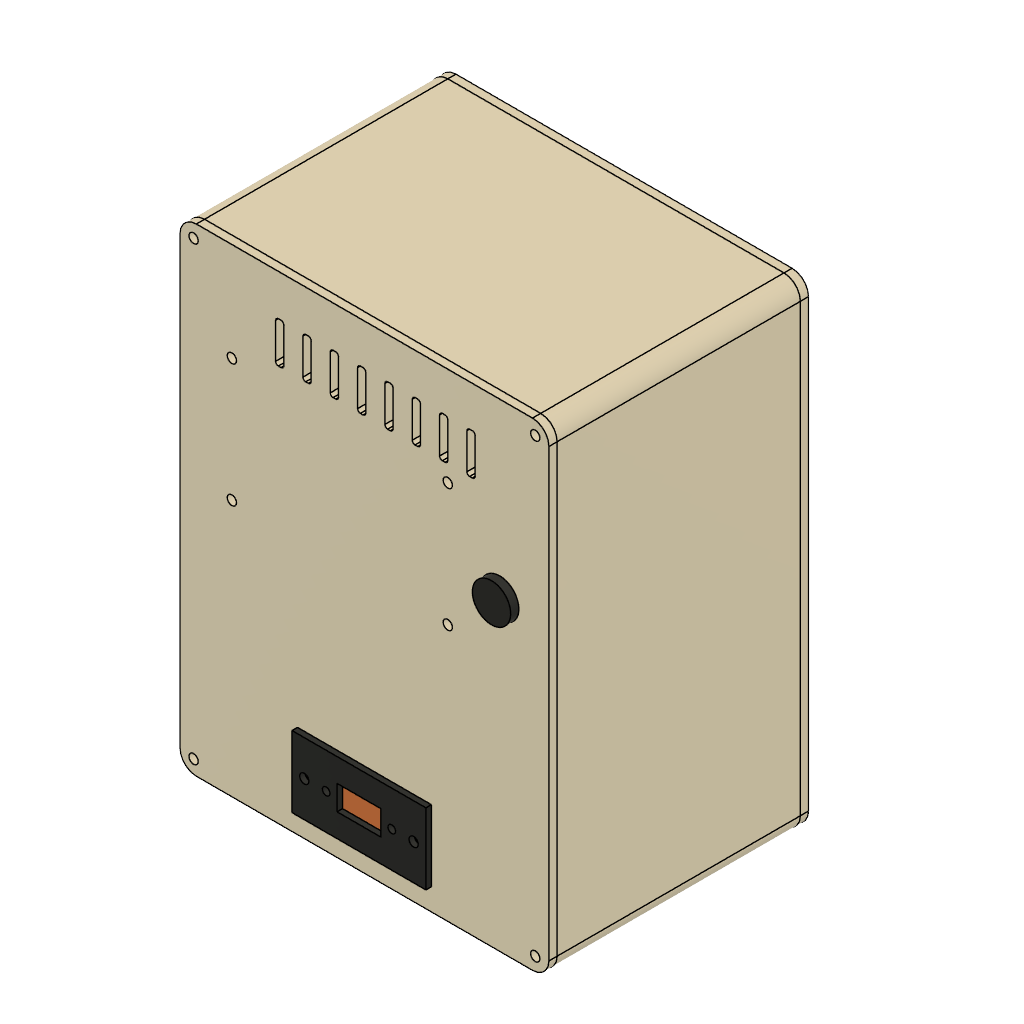
ORBIT-RevE (Autodesk Fusion 360 design; units mm, degrees)
part number: 2026-10-14-14-58-19-542
part number: 2026-10-14-14-58-21-077
part number: 2026-10-14-14-58-21-708
part number: 2026-10-14-14-58-23-821
part number: 2026-10-14-14-58-27-819
part number: 2026-10-14-14-58-51-787
part number: 2026-10-14-14-58-59-110
part number: 2026-10-14-14-59-02-449
part number: 2026-10-14-14-59-14-843
part number: 2026-10-14-14-59-18-859
part number: 2026-10-14-14-59-19-544
part number: 2026-10-14-14-59-20-250
part number: 2026-10-14-14-59-22-193
part number: 2026-10-14-14-59-22-958
part number: 2026-10-14-14-59-23-725
part number: 2026-10-14-14-59-25-713
part number: 2026-10-14-14-59-27-728
part number: 2026-10-14-14-59-28-510
part number: 2026-10-14-14-59-43-921
part number: 2026-10-14-14-59-48-721
part number: 2026-10-14-14-59-50-918
part number: 2026-10-14-14-59-55-353
part number: 2026-10-14-15-01-58-872
part number: 2026-10-14-15-01-59-865
part number: 2026-10-14-15-02-02-535
part number: 2026-10-14-15-02-03-536
part number: 2026-10-14-15-02-06-238
part number: 2026-10-14-15-02-08-109
part number: 2026-10-14-15-02-09-179
Autodesk Fusion 360 part; units mm, degrees
(part 1 of 2)
ref_plane "WorkPlane1" through (0, 0, 0) normal (0, 0, 1) x (1, 0, 0) in component "01 Ivory front panel"
sketch "Front panel" plane through (0, 0, 0) normal (0, 0, 1) x (1, 0, 0) in component "01 Ivory front panel"
  line L0 (6, 0) -> (129, 0)
  arc A0 (129, 0) -> (135, 6) centre (129, 6) ccw
  line L1 (135, 6) -> (135, 169)
  arc A1 (135, 169) -> (129, 175) centre (129, 169) ccw
  line L2 (129, 175) -> (6, 175)
  arc A2 (6, 175) -> (0, 169) centre (6, 169) ccw
  line L3 (0, 169) -> (0, 6)
  arc A3 (0, 6) -> (6, 0) centre (6, 6) ccw
extrude "Front panel (1)" add sketch "Front panel" along normal blind 3 makes body 1 in component "01 Ivory front panel"
ref_plane "WorkPlane2" through (0, 0, 0) normal (0, 0, 1) x (1, 0, 0) in component "01 Ivory front panel"
sketch "Adafruit 2050 landscape aperture" plane through (0, 0, 0) normal (0, 0, 1) x (1, 0, 0) in component "01 Ivory front panel"
  line L0 (30.9, 96.1) -> (104.1, 96.1)
  arc A0 (104.1, 96.1) -> (104.3, 96.3) centre (104.1, 96.3) ccw
  line L1 (104.3, 96.3) -> (104.3, 145.7)
  arc A1 (104.3, 145.7) -> (104.1, 145.9) centre (104.1, 145.7) ccw
  line L2 (104.1, 145.9) -> (30.9, 145.9)
  arc A2 (30.9, 145.9) -> (30.7, 145.7) centre (30.9, 145.7) ccw
  line L3 (30.7, 145.7) -> (30.7, 96.3)
  arc A3 (30.7, 96.3) -> (30.9, 96.1) centre (30.9, 96.3) ccw
extrude "Adafruit 2050 landscape aperture (1)" cut sketch "Adafruit 2050 landscape aperture" along normal blind 3 bodies 1 in component "01 Ivory front panel"
ref_plane "WorkPlane3" through (0, 0, 0) normal (0, 0, 1) x (1, 0, 0) in component "01 Ivory front panel"
sketch "Encoder" plane through (0, 0, 0) normal (0, 0, 1) x (1, 0, 0) in component "01 Ivory front panel"
  circle A0 centre (36, 36) radius 3.7
extrude "Encoder (1)" cut sketch "Encoder" along normal blind 3 bodies 1 in component "01 Ivory front panel"
ref_plane "WorkPlane4" through (0, 0, 0) normal (0, 0, 1) x (1, 0, 0) in component "01 Ivory front panel"
sketch "Pot" plane through (0, 0, 0) normal (0, 0, 1) x (1, 0, 0) in component "01 Ivory front panel"
  circle A0 centre (99, 36) radius 3.7
extrude "Pot (1)" cut sketch "Pot" along normal blind 3 bodies 1 in component "01 Ivory front panel"
ref_plane "WorkPlane5" through (0, 0, 0) normal (0, 0, 1) x (1, 0, 0) in component "01 Ivory front panel"
sketch "HOLD" plane through (0, 0, 0) normal (0, 0, 1) x (1, 0, 0) in component "01 Ivory front panel"
  circle A0 centre (18, 70) radius 3.2
extrude "HOLD (1)" cut sketch "HOLD" along normal blind 3 bodies 1 in component "01 Ivory front panel"
ref_plane "WorkPlane6" through (0, 0, 0) normal (0, 0, 1) x (1, 0, 0) in component "01 Ivory front panel"
sketch "GRID" plane through (0, 0, 0) normal (0, 0, 1) x (1, 0, 0) in component "01 Ivory front panel"
  circle A0 centre (117, 70) radius 3.2
extrude "GRID (1)" cut sketch "GRID" along normal blind 3 bodies 1 in component "01 Ivory front panel"
ref_plane "WorkPlane7" through (0, 0, 0) normal (0, 0, 1) x (1, 0, 0) in component "01 Ivory front panel"
sketch "Decorative disk slot" plane through (0, 0, 0) normal (0, 0, 1) x (1, 0, 0) in component "01 Ivory front panel"
  line L0 (51.5, 16) -> (83.5, 16)
  arc A0 (83.5, 16) -> (84.5, 17) centre (83.5, 17) ccw
  line L1 (84.5, 17) -> (84.5, 17.4)
  arc A1 (84.5, 17.4) -> (83.5, 18.4) centre (83.5, 17.4) ccw
  line L2 (83.5, 18.4) -> (51.5, 18.4)
  arc A2 (51.5, 18.4) -> (50.5, 17.4) centre (51.5, 17.4) ccw
  line L3 (50.5, 17.4) -> (50.5, 17)
  arc A3 (50.5, 17) -> (51.5, 16) centre (51.5, 17) ccw
extrude "Decorative disk slot (1)" cut sketch "Decorative disk slot" along normal blind 0.8 bodies 1 in component "01 Ivory front panel"
ref_plane "WorkPlane8" through (0, 0, 0) normal (0, 0, 1) x (1, 0, 0) in component "01 Ivory front panel"
sketch "M3 panel screw" plane through (0, 0, 0) normal (0, 0, 1) x (1, 0, 0) in component "01 Ivory front panel"
  circle A0 centre (5, 5) radius 1.7
extrude "M3 panel screw (1)" cut sketch "M3 panel screw" along normal blind 3 bodies 1 in component "01 Ivory front panel"
ref_plane "WorkPlane9" through (0, 0, 0) normal (0, 0, 1) x (1, 0, 0) in component "01 Ivory front panel"
sketch "M3 panel screw (1)" plane through (0, 0, 0) normal (0, 0, 1) x (1, 0, 0) in component "01 Ivory front panel"
  circle A0 centre (130, 5) radius 1.7
extrude "M3 panel screw (2)" cut sketch "M3 panel screw (1)" along normal blind 3 bodies 1 in component "01 Ivory front panel"
ref_plane "WorkPlane10" through (0, 0, 0) normal (0, 0, 1) x (1, 0, 0) in component "01 Ivory front panel"
sketch "M3 panel screw (2)" plane through (0, 0, 0) normal (0, 0, 1) x (1, 0, 0) in component "01 Ivory front panel"
  circle A0 centre (5, 170) radius 1.7
extrude "M3 panel screw (3)" cut sketch "M3 panel screw (2)" along normal blind 3 bodies 1 in component "01 Ivory front panel"
ref_plane "WorkPlane11" through (0, 0, 0) normal (0, 0, 1) x (1, 0, 0) in component "01 Ivory front panel"
sketch "M3 panel screw (3)" plane through (0, 0, 0) normal (0, 0, 1) x (1, 0, 0) in component "01 Ivory front panel"
  circle A0 centre (130, 170) radius 1.7
extrude "M3 panel screw (4)" cut sketch "M3 panel screw (3)" along normal blind 3 bodies 1 in component "01 Ivory front panel"
ref_plane "WorkPlane1" through (0, 0, 3) normal (0, 0, 1) x (1, 0, 0) in component "02 Ivory shell"
sketch "Shell exterior" plane through (0, 0, 3) normal (0, 0, 1) x (1, 0, 0) in component "02 Ivory shell"
  line L0 (6, 0) -> (129, 0)
  arc A0 (129, 0) -> (135, 6) centre (129, 6) ccw
  line L1 (135, 6) -> (135, 169)
  arc A1 (135, 169) -> (129, 175) centre (129, 169) ccw
  line L2 (129, 175) -> (6, 175)
  arc A2 (6, 175) -> (0, 169) centre (6, 169) ccw
  line L3 (0, 169) -> (0, 6)
  arc A3 (0, 6) -> (6, 0) centre (6, 6) ccw
extrude "Shell exterior (1)" add sketch "Shell exterior" along normal blind 89 separate body makes body 2 in component "02 Ivory shell"
ref_plane "WorkPlane2" through (0, 0, 3) normal (0, 0, 1) x (1, 0, 0) in component "02 Ivory shell"
sketch "Open cavity" plane through (0, 0, 3) normal (0, 0, 1) x (1, 0, 0) in component "02 Ivory shell"
  line L0 (6, 2.4) -> (129, 2.4)
  arc A0 (129, 2.4) -> (132.6, 6) centre (129, 6) ccw
  line L1 (132.6, 6) -> (132.6, 169)
  arc A1 (132.6, 169) -> (129, 172.6) centre (129, 169) ccw
  line L2 (129, 172.6) -> (6, 172.6)
  arc A2 (6, 172.6) -> (2.4, 169) centre (6, 169) ccw
  line L3 (2.4, 169) -> (2.4, 6)
  arc A3 (2.4, 6) -> (6, 2.4) centre (6, 6) ccw
extrude "Open cavity (1)" cut sketch "Open cavity" along normal blind 89 bodies 2 in component "02 Ivory shell"
ref_plane "WorkPlane3" through (0, 0, 3) normal (0, 0, 1) x (1, 0, 0) in component "02 Ivory shell"
sketch "M3 corner boss" plane through (0, 0, 3) normal (0, 0, 1) x (1, 0, 0) in component "02 Ivory shell"
  circle A0 centre (5, 5) radius 4
extrude "M3 corner boss (1)" add sketch "M3 corner boss" along normal blind 8 bodies 2 in component "02 Ivory shell"
ref_plane "WorkPlane4" through (0, 0, 3) normal (0, 0, 1) x (1, 0, 0) in component "02 Ivory shell"
sketch "M3 boss bore" plane through (0, 0, 3) normal (0, 0, 1) x (1, 0, 0) in component "02 Ivory shell"
  circle A0 centre (5, 5) radius 1.7
extrude "M3 boss bore (1)" cut sketch "M3 boss bore" along normal blind 8 bodies 2 in component "02 Ivory shell"
ref_plane "WorkPlane5" through (0, 0, 84) normal (0, 0, 1) x (1, 0, 0) in component "02 Ivory shell"
sketch "M3 corner boss (1)" plane through (0, 0, 84) normal (0, 0, 1) x (1, 0, 0) in component "02 Ivory shell"
  circle A0 centre (5, 5) radius 4
extrude "M3 corner boss (2)" add sketch "M3 corner boss (1)" along normal blind 8 bodies 2 in component "02 Ivory shell"
ref_plane "WorkPlane6" through (0, 0, 84) normal (0, 0, 1) x (1, 0, 0) in component "02 Ivory shell"
sketch "M3 boss bore (1)" plane through (0, 0, 84) normal (0, 0, 1) x (1, 0, 0) in component "02 Ivory shell"
  circle A0 centre (5, 5) radius 1.7
extrude "M3 boss bore (2)" cut sketch "M3 boss bore (1)" along normal blind 8 bodies 2 in component "02 Ivory shell"
ref_plane "WorkPlane7" through (0, 0, 3) normal (0, 0, 1) x (1, 0, 0) in component "02 Ivory shell"
sketch "M3 corner boss (2)" plane through (0, 0, 3) normal (0, 0, 1) x (1, 0, 0) in component "02 Ivory shell"
  circle A0 centre (130, 5) radius 4
extrude "M3 corner boss (3)" add sketch "M3 corner boss (2)" along normal blind 8 bodies 2 in component "02 Ivory shell"
ref_plane "WorkPlane8" through (0, 0, 3) normal (0, 0, 1) x (1, 0, 0) in component "02 Ivory shell"
sketch "M3 boss bore (2)" plane through (0, 0, 3) normal (0, 0, 1) x (1, 0, 0) in component "02 Ivory shell"
  circle A0 centre (130, 5) radius 1.7
extrude "M3 boss bore (3)" cut sketch "M3 boss bore (2)" along normal blind 8 bodies 2 in component "02 Ivory shell"
ref_plane "WorkPlane9" through (0, 0, 84) normal (0, 0, 1) x (1, 0, 0) in component "02 Ivory shell"
sketch "M3 corner boss (3)" plane through (0, 0, 84) normal (0, 0, 1) x (1, 0, 0) in component "02 Ivory shell"
  circle A0 centre (130, 5) radius 4
extrude "M3 corner boss (4)" add sketch "M3 corner boss (3)" along normal blind 8 bodies 2 in component "02 Ivory shell"
ref_plane "WorkPlane10" through (0, 0, 84) normal (0, 0, 1) x (1, 0, 0) in component "02 Ivory shell"
sketch "M3 boss bore (3)" plane through (0, 0, 84) normal (0, 0, 1) x (1, 0, 0) in component "02 Ivory shell"
  circle A0 centre (130, 5) radius 1.7
extrude "M3 boss bore (4)" cut sketch "M3 boss bore (3)" along normal blind 8 bodies 2 in component "02 Ivory shell"
ref_plane "WorkPlane11" through (0, 0, 3) normal (0, 0, 1) x (1, 0, 0) in component "02 Ivory shell"
sketch "M3 corner boss (4)" plane through (0, 0, 3) normal (0, 0, 1) x (1, 0, 0) in component "02 Ivory shell"
  circle A0 centre (5, 170) radius 4
extrude "M3 corner boss (5)" add sketch "M3 corner boss (4)" along normal blind 8 bodies 2 in component "02 Ivory shell"
ref_plane "WorkPlane12" through (0, 0, 3) normal (0, 0, 1) x (1, 0, 0) in component "02 Ivory shell"
sketch "M3 boss bore (4)" plane through (0, 0, 3) normal (0, 0, 1) x (1, 0, 0) in component "02 Ivory shell"
  circle A0 centre (5, 170) radius 1.7
extrude "M3 boss bore (5)" cut sketch "M3 boss bore (4)" along normal blind 8 bodies 2 in component "02 Ivory shell"
ref_plane "WorkPlane13" through (0, 0, 84) normal (0, 0, 1) x (1, 0, 0) in component "02 Ivory shell"
sketch "M3 corner boss (5)" plane through (0, 0, 84) normal (0, 0, 1) x (1, 0, 0) in component "02 Ivory shell"
  circle A0 centre (5, 170) radius 4
extrude "M3 corner boss (6)" add sketch "M3 corner boss (5)" along normal blind 8 bodies 2 in component "02 Ivory shell"
ref_plane "WorkPlane14" through (0, 0, 84) normal (0, 0, 1) x (1, 0, 0) in component "02 Ivory shell"
sketch "M3 boss bore (5)" plane through (0, 0, 84) normal (0, 0, 1) x (1, 0, 0) in component "02 Ivory shell"
  circle A0 centre (5, 170) radius 1.7
extrude "M3 boss bore (6)" cut sketch "M3 boss bore (5)" along normal blind 8 bodies 2 in component "02 Ivory shell"
ref_plane "WorkPlane15" through (0, 0, 3) normal (0, 0, 1) x (1, 0, 0) in component "02 Ivory shell"
sketch "M3 corner boss (6)" plane through (0, 0, 3) normal (0, 0, 1) x (1, 0, 0) in component "02 Ivory shell"
  circle A0 centre (130, 170) radius 4
extrude "M3 corner boss (7)" add sketch "M3 corner boss (6)" along normal blind 8 bodies 2 in component "02 Ivory shell"
ref_plane "WorkPlane16" through (0, 0, 3) normal (0, 0, 1) x (1, 0, 0) in component "02 Ivory shell"
sketch "M3 boss bore (6)" plane through (0, 0, 3) normal (0, 0, 1) x (1, 0, 0) in component "02 Ivory shell"
  circle A0 centre (130, 170) radius 1.7
extrude "M3 boss bore (7)" cut sketch "M3 boss bore (6)" along normal blind 8 bodies 2 in component "02 Ivory shell"
ref_plane "WorkPlane17" through (0, 0, 84) normal (0, 0, 1) x (1, 0, 0) in component "02 Ivory shell"
sketch "M3 corner boss (7)" plane through (0, 0, 84) normal (0, 0, 1) x (1, 0, 0) in component "02 Ivory shell"
  circle A0 centre (130, 170) radius 4
extrude "M3 corner boss (8)" add sketch "M3 corner boss (7)" along normal blind 8 bodies 2 in component "02 Ivory shell"
ref_plane "WorkPlane18" through (0, 0, 84) normal (0, 0, 1) x (1, 0, 0) in component "02 Ivory shell"
sketch "M3 boss bore (7)" plane through (0, 0, 84) normal (0, 0, 1) x (1, 0, 0) in component "02 Ivory shell"
  circle A0 centre (130, 170) radius 1.7
extrude "M3 boss bore (8)" cut sketch "M3 boss bore (7)" along normal blind 8 bodies 2 in component "02 Ivory shell"
ref_plane "WorkPlane1" through (0, 0, 92) normal (0, 0, 1) x (1, 0, 0) in component "03 Ivory rear cover"
sketch "Rear cover" plane through (0, 0, 92) normal (0, 0, 1) x (1, 0, 0) in component "03 Ivory rear cover"
  line L0 (6, 0) -> (129, 0)
  arc A0 (129, 0) -> (135, 6) centre (129, 6) ccw
  line L1 (135, 6) -> (135, 169)
  arc A1 (135, 169) -> (129, 175) centre (129, 169) ccw
  line L2 (129, 175) -> (6, 175)
  arc A2 (6, 175) -> (0, 169) centre (6, 169) ccw
  line L3 (0, 169) -> (0, 6)
  arc A3 (0, 6) -> (6, 0) centre (6, 6) ccw
extrude "Rear cover (1)" add sketch "Rear cover" along normal blind 3 separate body makes body 3 in component "03 Ivory rear cover"
ref_plane "WorkPlane2" through (0, 0, 92) normal (0, 0, 1) x (1, 0, 0) in component "03 Ivory rear cover"
sketch "Rear screw" plane through (0, 0, 92) normal (0, 0, 1) x (1, 0, 0) in component "03 Ivory rear cover"
  circle A0 centre (5, 5) radius 1.7
extrude "Rear screw (1)" cut sketch "Rear screw" along normal blind 3 bodies 3 in component "03 Ivory rear cover"
ref_plane "WorkPlane3" through (0, 0, 92) normal (0, 0, 1) x (1, 0, 0) in component "03 Ivory rear cover"
sketch "Rear screw (1)" plane through (0, 0, 92) normal (0, 0, 1) x (1, 0, 0) in component "03 Ivory rear cover"
  circle A0 centre (130, 5) radius 1.7
extrude "Rear screw (2)" cut sketch "Rear screw (1)" along normal blind 3 bodies 3 in component "03 Ivory rear cover"
ref_plane "WorkPlane4" through (0, 0, 92) normal (0, 0, 1) x (1, 0, 0) in component "03 Ivory rear cover"
sketch "Rear screw (2)" plane through (0, 0, 92) normal (0, 0, 1) x (1, 0, 0) in component "03 Ivory rear cover"
  circle A0 centre (5, 170) radius 1.7
extrude "Rear screw (3)" cut sketch "Rear screw (2)" along normal blind 3 bodies 3 in component "03 Ivory rear cover"
ref_plane "WorkPlane5" through (0, 0, 92) normal (0, 0, 1) x (1, 0, 0) in component "03 Ivory rear cover"
sketch "Rear screw (3)" plane through (0, 0, 92) normal (0, 0, 1) x (1, 0, 0) in component "03 Ivory rear cover"
  circle A0 centre (130, 170) radius 1.7
extrude "Rear screw (4)" cut sketch "Rear screw (3)" along normal blind 3 bodies 3 in component "03 Ivory rear cover"
ref_plane "WorkPlane6" through (0, 0, 92) normal (0, 0, 1) x (1, 0, 0) in component "03 Ivory rear cover"
sketch "Charge USB service opening" plane through (0, 0, 92) normal (0, 0, 1) x (1, 0, 0) in component "03 Ivory rear cover"
  line L0 (52.5, 12) -> (82.5, 12)
  arc A0 (82.5, 12) -> (84.5, 14) centre (82.5, 14) ccw
  line L1 (84.5, 14) -> (84.5, 28)
  arc A1 (84.5, 28) -> (82.5, 30) centre (82.5, 28) ccw
  line L2 (82.5, 30) -> (52.5, 30)
  arc A2 (52.5, 30) -> (50.5, 28) centre (52.5, 28) ccw
  line L3 (50.5, 28) -> (50.5, 14)
  arc A3 (50.5, 14) -> (52.5, 12) centre (52.5, 14) ccw
extrude "Charge USB service opening (1)" cut sketch "Charge USB service opening" along normal blind 3 bodies 3 in component "03 Ivory rear cover"
ref_plane "WorkPlane7" through (0, 0, 92) normal (0, 0, 1) x (1, 0, 0) in component "03 Ivory rear cover"
sketch "Rear vent" plane through (0, 0, 92) normal (0, 0, 1) x (1, 0, 0) in component "03 Ivory rear cover"
  line L0 (36, 145) -> (37, 145)
  arc A0 (37, 145) -> (38, 146) centre (37, 146) ccw
  line L1 (38, 146) -> (38, 159)
  arc A1 (38, 159) -> (37, 160) centre (37, 159) ccw
  line L2 (37, 160) -> (36, 160)
  arc A2 (36, 160) -> (35, 159) centre (36, 159) ccw
  line L3 (35, 159) -> (35, 146)
  arc A3 (35, 146) -> (36, 145) centre (36, 146) ccw
extrude "Rear vent (1)" cut sketch "Rear vent" along normal blind 3 bodies 3 in component "03 Ivory rear cover"
ref_plane "WorkPlane8" through (0, 0, 92) normal (0, 0, 1) x (1, 0, 0) in component "03 Ivory rear cover"
sketch "Rear vent (1)" plane through (0, 0, 92) normal (0, 0, 1) x (1, 0, 0) in component "03 Ivory rear cover"
  line L0 (46, 145) -> (47, 145)
  arc A0 (47, 145) -> (48, 146) centre (47, 146) ccw
  line L1 (48, 146) -> (48, 159)
  arc A1 (48, 159) -> (47, 160) centre (47, 159) ccw
  line L2 (47, 160) -> (46, 160)
  arc A2 (46, 160) -> (45, 159) centre (46, 159) ccw
  line L3 (45, 159) -> (45, 146)
  arc A3 (45, 146) -> (46, 145) centre (46, 146) ccw
extrude "Rear vent (2)" cut sketch "Rear vent (1)" along normal blind 3 bodies 3 in component "03 Ivory rear cover"
ref_plane "WorkPlane9" through (0, 0, 92) normal (0, 0, 1) x (1, 0, 0) in component "03 Ivory rear cover"
sketch "Rear vent (2)" plane through (0, 0, 92) normal (0, 0, 1) x (1, 0, 0) in component "03 Ivory rear cover"
  line L0 (56, 145) -> (57, 145)
  arc A0 (57, 145) -> (58, 146) centre (57, 146) ccw
  line L1 (58, 146) -> (58, 159)
  arc A1 (58, 159) -> (57, 160) centre (57, 159) ccw
  line L2 (57, 160) -> (56, 160)
  arc A2 (56, 160) -> (55, 159) centre (56, 159) ccw
  line L3 (55, 159) -> (55, 146)
  arc A3 (55, 146) -> (56, 145) centre (56, 146) ccw
extrude "Rear vent (3)" cut sketch "Rear vent (2)" along normal blind 3 bodies 3 in component "03 Ivory rear cover"
ref_plane "WorkPlane10" through (0, 0, 92) normal (0, 0, 1) x (1, 0, 0) in component "03 Ivory rear cover"
sketch "Rear vent (3)" plane through (0, 0, 92) normal (0, 0, 1) x (1, 0, 0) in component "03 Ivory rear cover"
  line L0 (66, 145) -> (67, 145)
  arc A0 (67, 145) -> (68, 146) centre (67, 146) ccw
  line L1 (68, 146) -> (68, 159)
  arc A1 (68, 159) -> (67, 160) centre (67, 159) ccw
  line L2 (67, 160) -> (66, 160)
  arc A2 (66, 160) -> (65, 159) centre (66, 159) ccw
  line L3 (65, 159) -> (65, 146)
  arc A3 (65, 146) -> (66, 145) centre (66, 146) ccw
extrude "Rear vent (4)" cut sketch "Rear vent (3)" along normal blind 3 bodies 3 in component "03 Ivory rear cover"
ref_plane "WorkPlane11" through (0, 0, 92) normal (0, 0, 1) x (1, 0, 0) in component "03 Ivory rear cover"
sketch "Rear vent (4)" plane through (0, 0, 92) normal (0, 0, 1) x (1, 0, 0) in component "03 Ivory rear cover"
  line L0 (76, 145) -> (77, 145)
  arc A0 (77, 145) -> (78, 146) centre (77, 146) ccw
  line L1 (78, 146) -> (78, 159)
  arc A1 (78, 159) -> (77, 160) centre (77, 159) ccw
  line L2 (77, 160) -> (76, 160)
  arc A2 (76, 160) -> (75, 159) centre (76, 159) ccw
  line L3 (75, 159) -> (75, 146)
  arc A3 (75, 146) -> (76, 145) centre (76, 146) ccw
extrude "Rear vent (5)" cut sketch "Rear vent (4)" along normal blind 3 bodies 3 in component "03 Ivory rear cover"
ref_plane "WorkPlane12" through (0, 0, 92) normal (0, 0, 1) x (1, 0, 0) in component "03 Ivory rear cover"
sketch "Rear vent (5)" plane through (0, 0, 92) normal (0, 0, 1) x (1, 0, 0) in component "03 Ivory rear cover"
  line L0 (86, 145) -> (87, 145)
  arc A0 (87, 145) -> (88, 146) centre (87, 146) ccw
  line L1 (88, 146) -> (88, 159)
  arc A1 (88, 159) -> (87, 160) centre (87, 159) ccw
  line L2 (87, 160) -> (86, 160)
  arc A2 (86, 160) -> (85, 159) centre (86, 159) ccw
  line L3 (85, 159) -> (85, 146)
  arc A3 (85, 146) -> (86, 145) centre (86, 146) ccw
extrude "Rear vent (6)" cut sketch "Rear vent (5)" along normal blind 3 bodies 3 in component "03 Ivory rear cover"
ref_plane "WorkPlane13" through (0, 0, 92) normal (0, 0, 1) x (1, 0, 0) in component "03 Ivory rear cover"
sketch "Rear vent (6)" plane through (0, 0, 92) normal (0, 0, 1) x (1, 0, 0) in component "03 Ivory rear cover"
  line L0 (96, 145) -> (97, 145)
  arc A0 (97, 145) -> (98, 146) centre (97, 146) ccw
  line L1 (98, 146) -> (98, 159)
  arc A1 (98, 159) -> (97, 160) centre (97, 159) ccw
  line L2 (97, 160) -> (96, 160)
  arc A2 (96, 160) -> (95, 159) centre (96, 159) ccw
  line L3 (95, 159) -> (95, 146)
  arc A3 (95, 146) -> (96, 145) centre (96, 146) ccw
extrude "Rear vent (7)" cut sketch "Rear vent (6)" along normal blind 3 bodies 3 in component "03 Ivory rear cover"
ref_plane "WorkPlane14" through (0, 0, 92) normal (0, 0, 1) x (1, 0, 0) in component "03 Ivory rear cover"
sketch "Rear vent (7)" plane through (0, 0, 92) normal (0, 0, 1) x (1, 0, 0) in component "03 Ivory rear cover"
  line L0 (106, 145) -> (107, 145)
  arc A0 (107, 145) -> (108, 146) centre (107, 146) ccw
  line L1 (108, 146) -> (108, 159)
  arc A1 (108, 159) -> (107, 160) centre (107, 159) ccw
  line L2 (107, 160) -> (106, 160)
  arc A2 (106, 160) -> (105, 159) centre (106, 159) ccw
  line L3 (105, 159) -> (105, 146)
  arc A3 (105, 146) -> (106, 145) centre (106, 146) ccw
extrude "Rear vent (8)" cut sketch "Rear vent (7)" along normal blind 3 bodies 3 in component "03 Ivory rear cover"
ref_plane "WorkPlane15" through (0, 0, 92) normal (0, 0, 1) x (1, 0, 0) in component "03 Ivory rear cover"
sketch "12mm latching power switch clearance" plane through (0, 0, 92) normal (0, 0, 1) x (1, 0, 0) in component "03 Ivory rear cover"
  circle A0 centre (117, 112) radius 6.1
extrude "12mm latching power switch clearance (1)" cut sketch "12mm latching power switch clearance" along normal blind 3 bodies 3 in component "03 Ivory rear cover"
ref_plane "WorkPlane1" through (0, 0, -2) normal (0, 0, 1) x (1, 0, 0) in component "04 Charcoal landscape bezel"
sketch "Landscape display bezel" plane through (0, 0, -2) normal (0, 0, 1) x (1, 0, 0) in component "04 Charcoal landscape bezel"
  line L0 (29.7, 92.1) -> (105.3, 92.1)
  arc A0 (105.3, 92.1) -> (108.3, 95.1) centre (105.3, 95.1) ccw
  line L1 (108.3, 95.1) -> (108.3, 146.9)
  arc A1 (108.3, 146.9) -> (105.3, 149.9) centre (105.3, 146.9) ccw
  line L2 (105.3, 149.9) -> (29.7, 149.9)
  arc A2 (29.7, 149.9) -> (26.7, 146.9) centre (29.7, 146.9) ccw
  line L3 (26.7, 146.9) -> (26.7, 95.1)
  arc A3 (26.7, 95.1) -> (29.7, 92.1) centre (29.7, 95.1) ccw
extrude "Landscape display bezel (1)" add sketch "Landscape display bezel" along normal blind 2 separate body makes body 4 in component "04 Charcoal landscape bezel"
ref_plane "WorkPlane2" through (0, 0, -2) normal (0, 0, 1) x (1, 0, 0) in component "04 Charcoal landscape bezel"
sketch "Visible aperture" plane through (0, 0, -2) normal (0, 0, 1) x (1, 0, 0) in component "04 Charcoal landscape bezel"
  line L0 (30.9, 96.1) -> (104.1, 96.1)
  arc A0 (104.1, 96.1) -> (104.3, 96.3) centre (104.1, 96.3) ccw
  line L1 (104.3, 96.3) -> (104.3, 145.7)
  arc A1 (104.3, 145.7) -> (104.1, 145.9) centre (104.1, 145.7) ccw
  line L2 (104.1, 145.9) -> (30.9, 145.9)
  arc A2 (30.9, 145.9) -> (30.7, 145.7) centre (30.9, 145.7) ccw
  line L3 (30.7, 145.7) -> (30.7, 96.3)
  arc A3 (30.7, 96.3) -> (30.9, 96.1) centre (30.9, 96.3) ccw
extrude "Visible aperture (1)" cut sketch "Visible aperture" along normal blind 2 bodies 4 in component "04 Charcoal landscape bezel"
ref_plane "WorkPlane3" through (0, 0, 0) normal (0, 0, 1) x (1, 0, 0) in component "04 Charcoal landscape bezel"
sketch "Bezel peg" plane through (0, 0, 0) normal (0, 0, 1) x (1, 0, 0) in component "04 Charcoal landscape bezel"
  circle A0 centre (28.7, 94.1) radius 0.9
extrude "Bezel peg (1)" add sketch "Bezel peg" along normal blind 2 bodies 4 in component "04 Charcoal landscape bezel"
ref_plane "WorkPlane12" through (0, 0, 0) normal (0, 0, 1) x (1, 0, 0) in component "01 Ivory front panel"
sketch "Bezel socket" plane through (0, 0, 0) normal (0, 0, 1) x (1, 0, 0) in component "01 Ivory front panel"
  circle A0 centre (28.7, 94.1) radius 1.1
extrude "Bezel socket (1)" cut sketch "Bezel socket" along normal blind 2.2 bodies 1 in component "01 Ivory front panel"
extrude "Extrude4" cut sketch "Bezel socket" along normal blind 2.2 bodies 4 in component "04 Charcoal landscape bezel"
ref_plane "WorkPlane4" through (0, 0, 0) normal (0, 0, 1) x (1, 0, 0) in component "04 Charcoal landscape bezel"
sketch "Bezel peg (1)" plane through (0, 0, 0) normal (0, 0, 1) x (1, 0, 0) in component "04 Charcoal landscape bezel"
  circle A0 centre (106.3, 147.9) radius 0.9
extrude "Bezel peg (2)" add sketch "Bezel peg (1)" along normal blind 2 bodies 4 in component "04 Charcoal landscape bezel"
ref_plane "WorkPlane13" through (0, 0, 0) normal (0, 0, 1) x (1, 0, 0) in component "01 Ivory front panel"
sketch "Bezel socket (1)" plane through (0, 0, 0) normal (0, 0, 1) x (1, 0, 0) in component "01 Ivory front panel"
  circle A0 centre (106.3, 147.9) radius 1.1
extrude "Bezel socket (2)" cut sketch "Bezel socket (1)" along normal blind 2.2 bodies 1 in component "01 Ivory front panel"
extrude "Extrude6" cut sketch "Bezel socket (1)" along normal blind 2.2 bodies 4 in component "04 Charcoal landscape bezel"
ref_plane "WorkPlane14" through (0, 0, 3) normal (0, 0, 1) x (1, 0, 0) in component "01 Ivory front panel"
sketch "Display PCB mounting boss - verify stack" plane through (0, 0, 3) normal (0, 0, 1) x (1, 0, 0) in component "01 Ivory front panel"
  circle A0 centre (18.83, 90.52) radius 3.4
extrude "Display PCB mounting boss - verify stack (1)" add sketch "Display PCB mounting boss - verify stack" along normal blind 4.8 bodies 1 in component "01 Ivory front panel"
ref_plane "WorkPlane15" through (0, 0, 3.8) normal (0, 0, 1) x (1, 0, 0) in component "01 Ivory front panel"
sketch "M2.5 insert pilot - calibrate" plane through (0, 0, 3.8) normal (0, 0, 1) x (1, 0, 0) in component "01 Ivory front panel"
  circle A0 centre (18.83, 90.52) radius 1.65
extrude "M2.5 insert pilot - calibrate (1)" cut sketch "M2.5 insert pilot - calibrate" along normal blind 4 bodies 1 in component "01 Ivory front panel"
ref_plane "WorkPlane16" through (0, 0, 3) normal (0, 0, 1) x (1, 0, 0) in component "01 Ivory front panel"
sketch "Display PCB mounting boss - verify stack (1)" plane through (0, 0, 3) normal (0, 0, 1) x (1, 0, 0) in component "01 Ivory front panel"
  circle A0 centre (18.83, 151.48) radius 3.4
extrude "Display PCB mounting boss - verify stack (2)" add sketch "Display PCB mounting boss - verify stack (1)" along normal blind 4.8 bodies 1 in component "01 Ivory front panel"
ref_plane "WorkPlane17" through (0, 0, 3.8) normal (0, 0, 1) x (1, 0, 0) in component "01 Ivory front panel"
sketch "M2.5 insert pilot - calibrate (1)" plane through (0, 0, 3.8) normal (0, 0, 1) x (1, 0, 0) in component "01 Ivory front panel"
  circle A0 centre (18.83, 151.48) radius 1.65
extrude "M2.5 insert pilot - calibrate (2)" cut sketch "M2.5 insert pilot - calibrate (1)" along normal blind 4 bodies 1 in component "01 Ivory front panel"
ref_plane "WorkPlane18" through (0, 0, 3) normal (0, 0, 1) x (1, 0, 0) in component "01 Ivory front panel"
sketch "Display PCB mounting boss - verify stack (2)" plane through (0, 0, 3) normal (0, 0, 1) x (1, 0, 0) in component "01 Ivory front panel"
  circle A0 centre (110.27, 90.52) radius 3.4
extrude "Display PCB mounting boss - verify stack (3)" add sketch "Display PCB mounting boss - verify stack (2)" along normal blind 4.8 bodies 1 in component "01 Ivory front panel"
ref_plane "WorkPlane19" through (0, 0, 3.8) normal (0, 0, 1) x (1, 0, 0) in component "01 Ivory front panel"
sketch "M2.5 insert pilot - calibrate (2)" plane through (0, 0, 3.8) normal (0, 0, 1) x (1, 0, 0) in component "01 Ivory front panel"
  circle A0 centre (110.27, 90.52) radius 1.65
extrude "M2.5 insert pilot - calibrate (3)" cut sketch "M2.5 insert pilot - calibrate (2)" along normal blind 4 bodies 1 in component "01 Ivory front panel"
ref_plane "WorkPlane20" through (0, 0, 3) normal (0, 0, 1) x (1, 0, 0) in component "01 Ivory front panel"
sketch "Display PCB mounting boss - verify stack (3)" plane through (0, 0, 3) normal (0, 0, 1) x (1, 0, 0) in component "01 Ivory front panel"
  circle A0 centre (110.27, 151.48) radius 3.4
extrude "Display PCB mounting boss - verify stack (4)" add sketch "Display PCB mounting boss - verify stack (3)" along normal blind 4.8 bodies 1 in component "01 Ivory front panel"
ref_plane "WorkPlane21" through (0, 0, 3.8) normal (0, 0, 1) x (1, 0, 0) in component "01 Ivory front panel"
sketch "M2.5 insert pilot - calibrate (3)" plane through (0, 0, 3.8) normal (0, 0, 1) x (1, 0, 0) in component "01 Ivory front panel"
  circle A0 centre (110.27, 151.48) radius 1.65
extrude "M2.5 insert pilot - calibrate (4)" cut sketch "M2.5 insert pilot - calibrate (3)" along normal blind 4 bodies 1 in component "01 Ivory front panel"
ref_plane "WorkPlane1" through (0, 0, 55) normal (0, 0, 1) x (1, 0, 0) in component "05 Controller and charger tray"
sketch "Removable electronics tray" plane through (0, 0, 55) normal (0, 0, 1) x (1, 0, 0) in component "05 Controller and charger tray"
  line L0 (15.5, 10) -> (119.5, 10)
  arc A0 (119.5, 10) -> (122.5, 13) centre (119.5, 13) ccw
  line L1 (122.5, 13) -> (122.5, 77)
  arc A1 (122.5, 77) -> (119.5, 80) centre (119.5, 77) ccw
  line L2 (119.5, 80) -> (15.5, 80)
  arc A2 (15.5, 80) -> (12.5, 77) centre (15.5, 77) ccw
  line L3 (12.5, 77) -> (12.5, 13)
  arc A3 (12.5, 13) -> (15.5, 10) centre (15.5, 13) ccw
extrude "Removable electronics tray (1)" add sketch "Removable electronics tray" along normal blind 3 separate body makes body 5 in component "05 Controller and charger tray"
ref_plane "WorkPlane2" through (0, 0, 55) normal (0, 0, 1) x (1, 0, 0) in component "05 Controller and charger tray"
sketch "M3 tray screw" plane through (0, 0, 55) normal (0, 0, 1) x (1, 0, 0) in component "05 Controller and charger tray"
  circle A0 centre (17.5, 20) radius 1.7
extrude "M3 tray screw (1)" cut sketch "M3 tray screw" along normal blind 3 bodies 5 in component "05 Controller and charger tray"
ref_plane "WorkPlane19" through (0, 0, 48) normal (0, 0, 1) x (1, 0, 0) in component "02 Ivory shell"
sketch "Tray ledge" plane through (0, 0, 48) normal (0, 0, 1) x (1, 0, 0) in component "02 Ivory shell"
  line L0 (1, 14) -> (24, 14)
  line L1 (24, 14) -> (24, 26)
  line L2 (24, 26) -> (1, 26)
  line L3 (1, 26) -> (1, 14)
extrude "Tray ledge (1)" add sketch "Tray ledge" along normal blind 7 bodies 2 in component "02 Ivory shell"
ref_plane "WorkPlane20" through (0, 0, 50) normal (0, 0, 1) x (1, 0, 0) in component "02 Ivory shell"
sketch "M3 insert pilot" plane through (0, 0, 50) normal (0, 0, 1) x (1, 0, 0) in component "02 Ivory shell"
  circle A0 centre (17.5, 20) radius 2.2
extrude "M3 insert pilot (1)" cut sketch "M3 insert pilot" along normal blind 5 bodies 2 in component "02 Ivory shell"
ref_plane "WorkPlane3" through (0, 0, 55) normal (0, 0, 1) x (1, 0, 0) in component "05 Controller and charger tray"
sketch "M3 tray screw (1)" plane through (0, 0, 55) normal (0, 0, 1) x (1, 0, 0) in component "05 Controller and charger tray"
  circle A0 centre (17.5, 70) radius 1.7
extrude "M3 tray screw (2)" cut sketch "M3 tray screw (1)" along normal blind 3 bodies 5 in component "05 Controller and charger tray"
ref_plane "WorkPlane21" through (0, 0, 48) normal (0, 0, 1) x (1, 0, 0) in component "02 Ivory shell"
sketch "Tray ledge (1)" plane through (0, 0, 48) normal (0, 0, 1) x (1, 0, 0) in component "02 Ivory shell"
  line L0 (1, 64) -> (24, 64)
  line L1 (24, 64) -> (24, 76)
  line L2 (24, 76) -> (1, 76)
  line L3 (1, 76) -> (1, 64)
extrude "Tray ledge (2)" add sketch "Tray ledge (1)" along normal blind 7 bodies 2 in component "02 Ivory shell"
ref_plane "WorkPlane22" through (0, 0, 50) normal (0, 0, 1) x (1, 0, 0) in component "02 Ivory shell"
sketch "M3 insert pilot (1)" plane through (0, 0, 50) normal (0, 0, 1) x (1, 0, 0) in component "02 Ivory shell"
  circle A0 centre (17.5, 70) radius 2.2
extrude "M3 insert pilot (2)" cut sketch "M3 insert pilot (1)" along normal blind 5 bodies 2 in component "02 Ivory shell"
ref_plane "WorkPlane4" through (0, 0, 55) normal (0, 0, 1) x (1, 0, 0) in component "05 Controller and charger tray"
sketch "M3 tray screw (2)" plane through (0, 0, 55) normal (0, 0, 1) x (1, 0, 0) in component "05 Controller and charger tray"
  circle A0 centre (117.5, 20) radius 1.7
extrude "M3 tray screw (3)" cut sketch "M3 tray screw (2)" along normal blind 3 bodies 5 in component "05 Controller and charger tray"
ref_plane "WorkPlane23" through (0, 0, 48) normal (0, 0, 1) x (1, 0, 0) in component "02 Ivory shell"
sketch "Tray ledge (2)" plane through (0, 0, 48) normal (0, 0, 1) x (1, 0, 0) in component "02 Ivory shell"
  line L0 (111, 14) -> (134, 14)
  line L1 (134, 14) -> (134, 26)
  line L2 (134, 26) -> (111, 26)
  line L3 (111, 26) -> (111, 14)
extrude "Tray ledge (3)" add sketch "Tray ledge (2)" along normal blind 7 bodies 2 in component "02 Ivory shell"
ref_plane "WorkPlane24" through (0, 0, 50) normal (0, 0, 1) x (1, 0, 0) in component "02 Ivory shell"
sketch "M3 insert pilot (2)" plane through (0, 0, 50) normal (0, 0, 1) x (1, 0, 0) in component "02 Ivory shell"
  circle A0 centre (117.5, 20) radius 2.2
extrude "M3 insert pilot (3)" cut sketch "M3 insert pilot (2)" along normal blind 5 bodies 2 in component "02 Ivory shell"
ref_plane "WorkPlane5" through (0, 0, 55) normal (0, 0, 1) x (1, 0, 0) in component "05 Controller and charger tray"
sketch "M3 tray screw (3)" plane through (0, 0, 55) normal (0, 0, 1) x (1, 0, 0) in component "05 Controller and charger tray"
  circle A0 centre (117.5, 70) radius 1.7
extrude "M3 tray screw (4)" cut sketch "M3 tray screw (3)" along normal blind 3 bodies 5 in component "05 Controller and charger tray"
ref_plane "WorkPlane25" through (0, 0, 48) normal (0, 0, 1) x (1, 0, 0) in component "02 Ivory shell"
sketch "Tray ledge (3)" plane through (0, 0, 48) normal (0, 0, 1) x (1, 0, 0) in component "02 Ivory shell"
  line L0 (111, 64) -> (134, 64)
  line L1 (134, 64) -> (134, 76)
  line L2 (134, 76) -> (111, 76)
  line L3 (111, 76) -> (111, 64)
extrude "Tray ledge (4)" add sketch "Tray ledge (3)" along normal blind 7 bodies 2 in component "02 Ivory shell"
ref_plane "WorkPlane26" through (0, 0, 50) normal (0, 0, 1) x (1, 0, 0) in component "02 Ivory shell"
sketch "M3 insert pilot (3)" plane through (0, 0, 50) normal (0, 0, 1) x (1, 0, 0) in component "02 Ivory shell"
  circle A0 centre (117.5, 70) radius 2.2
extrude "M3 insert pilot (4)" cut sketch "M3 insert pilot (3)" along normal blind 5 bodies 2 in component "02 Ivory shell"
ref_plane "WorkPlane6" through (0, 0, 55) normal (0, 0, 1) x (1, 0, 0) in component "05 Controller and charger tray"
sketch "ESP32 antenna keepout" plane through (0, 0, 55) normal (0, 0, 1) x (1, 0, 0) in component "05 Controller and charger tray"
  line L0 (26, 63) -> (58, 63)
  arc A0 (58, 63) -> (59, 64) centre (58, 64) ccw
  line L1 (59, 64) -> (59, 76)
  arc A1 (59, 76) -> (58, 77) centre (58, 76) ccw
  line L2 (58, 77) -> (26, 77)
  arc A2 (26, 77) -> (25, 76) centre (26, 76) ccw
  line L3 (25, 76) -> (25, 64)
  arc A3 (25, 64) -> (26, 63) centre (26, 64) ccw
extrude "ESP32 antenna keepout (1)" cut sketch "ESP32 antenna keepout" along normal blind 3 bodies 5 in component "05 Controller and charger tray"
ref_plane "WorkPlane7" through (0, 0, 55) normal (0, 0, 1) x (1, 0, 0) in component "05 Controller and charger tray"
sketch "M2.5 board fixing" plane through (0, 0, 55) normal (0, 0, 1) x (1, 0, 0) in component "05 Controller and charger tray"
  circle A0 centre (29, 16) radius 1.4
extrude "M2.5 board fixing (1)" cut sketch "M2.5 board fixing" along normal blind 3 bodies 5 in component "05 Controller and charger tray"
ref_plane "WorkPlane8" through (0, 0, 55) normal (0, 0, 1) x (1, 0, 0) in component "05 Controller and charger tray"
sketch "M2.5 board fixing (1)" plane through (0, 0, 55) normal (0, 0, 1) x (1, 0, 0) in component "05 Controller and charger tray"
  circle A0 centre (29, 57) radius 1.4
extrude "M2.5 board fixing (2)" cut sketch "M2.5 board fixing (1)" along normal blind 3 bodies 5 in component "05 Controller and charger tray"
ref_plane "WorkPlane9" through (0, 0, 55) normal (0, 0, 1) x (1, 0, 0) in component "05 Controller and charger tray"
sketch "M2.5 board fixing (2)" plane through (0, 0, 55) normal (0, 0, 1) x (1, 0, 0) in component "05 Controller and charger tray"
  circle A0 centre (56, 16) radius 1.4
extrude "M2.5 board fixing (3)" cut sketch "M2.5 board fixing (2)" along normal blind 3 bodies 5 in component "05 Controller and charger tray"
ref_plane "WorkPlane10" through (0, 0, 55) normal (0, 0, 1) x (1, 0, 0) in component "05 Controller and charger tray"
sketch "M2.5 board fixing (3)" plane through (0, 0, 55) normal (0, 0, 1) x (1, 0, 0) in component "05 Controller and charger tray"
  circle A0 centre (56, 57) radius 1.4
extrude "M2.5 board fixing (4)" cut sketch "M2.5 board fixing (3)" along normal blind 3 bodies 5 in component "05 Controller and charger tray"
ref_plane "WorkPlane11" through (0, 0, 55) normal (0, 0, 1) x (1, 0, 0) in component "05 Controller and charger tray"
sketch "M2.5 board fixing (4)" plane through (0, 0, 55) normal (0, 0, 1) x (1, 0, 0) in component "05 Controller and charger tray"
  circle A0 centre (72.54, 25.54) radius 1.4
extrude "M2.5 board fixing (5)" cut sketch "M2.5 board fixing (4)" along normal blind 3 bodies 5 in component "05 Controller and charger tray"
ref_plane "WorkPlane12" through (0, 0, 55) normal (0, 0, 1) x (1, 0, 0) in component "05 Controller and charger tray"
sketch "M2.5 board fixing (5)" plane through (0, 0, 55) normal (0, 0, 1) x (1, 0, 0) in component "05 Controller and charger tray"
  circle A0 centre (72.54, 43.32) radius 1.4
extrude "M2.5 board fixing (6)" cut sketch "M2.5 board fixing (5)" along normal blind 3 bodies 5 in component "05 Controller and charger tray"
ref_plane "WorkPlane1" through (0, 0, 95) normal (0, 0, 1) x (1, 0, 0) in component "07 Replaceable USB charge adapter - generic 24mm pitch"
sketch "Replaceable USB adapter" plane through (0, 0, 95) normal (0, 0, 1) x (1, 0, 0) in component "07 Replaceable USB charge adapter - generic 24mm pitch"
  line L0 (43, 8) -> (92, 8)
  line L1 (92, 8) -> (92, 34)
  line L2 (92, 34) -> (43, 34)
  line L3 (43, 34) -> (43, 8)
extrude "Replaceable USB adapter (1)" add sketch "Replaceable USB adapter" along normal blind 2 separate body makes body 6 in component "07 Replaceable USB charge adapter - generic 24mm pitch"
ref_plane "WorkPlane2" through (0, 0, 95) normal (0, 0, 1) x (1, 0, 0) in component "07 Replaceable USB charge adapter - generic 24mm pitch"
sketch "USB cutout - match purchased extension" plane through (0, 0, 95) normal (0, 0, 1) x (1, 0, 0) in component "07 Replaceable USB charge adapter - generic 24mm pitch"
  line L0 (59.5, 16.5) -> (75.5, 16.5)
  line L1 (75.5, 16.5) -> (75.5, 25.5)
  line L2 (75.5, 25.5) -> (59.5, 25.5)
  line L3 (59.5, 25.5) -> (59.5, 16.5)
extrude "USB cutout - match purchased extension (1)" cut sketch "USB cutout - match purchased extension" along normal blind 2 bodies 6 in component "07 Replaceable USB charge adapter - generic 24mm pitch"
ref_plane "WorkPlane3" through (0, 0, 95) normal (0, 0, 1) x (1, 0, 0) in component "07 Replaceable USB charge adapter - generic 24mm pitch"
sketch "Adapter M3 fixing" plane through (0, 0, 95) normal (0, 0, 1) x (1, 0, 0) in component "07 Replaceable USB charge adapter - generic 24mm pitch"
  circle A0 centre (47.5, 21) radius 1.7
extrude "Adapter M3 fixing (1)" cut sketch "Adapter M3 fixing" along normal blind 2 bodies 6 in component "07 Replaceable USB charge adapter - generic 24mm pitch"
ref_plane "WorkPlane16" through (0, 0, 92) normal (0, 0, 1) x (1, 0, 0) in component "03 Ivory rear cover"
sketch "Adapter M3 fixing (2)" plane through (0, 0, 92) normal (0, 0, 1) x (1, 0, 0) in component "03 Ivory rear cover"
  circle A0 centre (47.5, 21) radius 1.7
extrude "Adapter M3 fixing (1)'" cut sketch "Adapter M3 fixing (2)" along normal blind 3 bodies 3 in component "03 Ivory rear cover"
ref_plane "WorkPlane4" through (0, 0, 95) normal (0, 0, 1) x (1, 0, 0) in component "07 Replaceable USB charge adapter - generic 24mm pitch"
sketch "Adapter M3 fixing (1)" plane through (0, 0, 95) normal (0, 0, 1) x (1, 0, 0) in component "07 Replaceable USB charge adapter - generic 24mm pitch"
  circle A0 centre (87.5, 21) radius 1.7
extrude "Adapter M3 fixing (2)" cut sketch "Adapter M3 fixing (1)" along normal blind 2 bodies 6 in component "07 Replaceable USB charge adapter - generic 24mm pitch"
ref_plane "WorkPlane17" through (0, 0, 92) normal (0, 0, 1) x (1, 0, 0) in component "03 Ivory rear cover"
sketch "Adapter M3 fixing (1) (2)" plane through (0, 0, 92) normal (0, 0, 1) x (1, 0, 0) in component "03 Ivory rear cover"
  circle A0 centre (87.5, 21) radius 1.7
extrude "Adapter M3 fixing (2)'" cut sketch "Adapter M3 fixing (1) (2)" along normal blind 3 bodies 3 in component "03 Ivory rear cover"
ref_plane "WorkPlane5" through (0, 0, 95) normal (0, 0, 1) x (1, 0, 0) in component "07 Replaceable USB charge adapter - generic 24mm pitch"
sketch "USB flange fixing" plane through (0, 0, 95) normal (0, 0, 1) x (1, 0, 0) in component "07 Replaceable USB charge adapter - generic 24mm pitch"
  circle A0 centre (55.5, 21) radius 1.4
extrude "USB flange fixing (1)" cut sketch "USB flange fixing" along normal blind 2 bodies 6 in component "07 Replaceable USB charge adapter - generic 24mm pitch"
ref_plane "WorkPlane6" through (0, 0, 95) normal (0, 0, 1) x (1, 0, 0) in component "07 Replaceable USB charge adapter - generic 24mm pitch"
sketch "USB flange fixing (1)" plane through (0, 0, 95) normal (0, 0, 1) x (1, 0, 0) in component "07 Replaceable USB charge adapter - generic 24mm pitch"
  circle A0 centre (79.5, 21) radius 1.4
extrude "USB flange fixing (2)" cut sketch "USB flange fixing (1)" along normal blind 2 bodies 6 in component "07 Replaceable USB charge adapter - generic 24mm pitch"
ref_plane "WorkPlane1" through (0, 0, 88) normal (0, 0, 1) x (1, 0, 0) in component "08 Removable battery cradle"
sketch "Battery backplate" plane through (0, 0, 88) normal (0, 0, 1) x (1, 0, 0) in component "08 Removable battery cradle"
  line L0 (16, 91) -> (101, 91)
  line L1 (101, 91) -> (101, 142)
  line L2 (101, 142) -> (16, 142)
  line L3 (16, 142) -> (16, 91)
extrude "Battery backplate (1)" add sketch "Battery backplate" along normal blind 2 separate body makes body 7 in component "08 Removable battery cradle"
ref_plane "WorkPlane2" through (0, 0, 66) normal (0, 0, 1) x (1, 0, 0) in component "08 Removable battery cradle"
sketch "Pack end guard" plane through (0, 0, 66) normal (0, 0, 1) x (1, 0, 0) in component "08 Removable battery cradle"
  line L0 (16, 99) -> (19, 99)
  line L1 (19, 99) -> (19, 133)
  line L2 (19, 133) -> (16, 133)
  line L3 (16, 133) -> (16, 99)
extrude "Pack end guard (1)" add sketch "Pack end guard" along normal blind 22 bodies 7 in component "08 Removable battery cradle"
ref_plane "WorkPlane3" through (0, 0, 66) normal (0, 0, 1) x (1, 0, 0) in component "08 Removable battery cradle"
sketch "Pack end guard (1)" plane through (0, 0, 66) normal (0, 0, 1) x (1, 0, 0) in component "08 Removable battery cradle"
  line L0 (98, 99) -> (101, 99)
  line L1 (101, 99) -> (101, 133)
  line L2 (101, 133) -> (98, 133)
  line L3 (98, 133) -> (98, 99)
extrude "Pack end guard (2)" add sketch "Pack end guard (1)" along normal blind 22 bodies 7 in component "08 Removable battery cradle"
ref_plane "WorkPlane4" through (0, 0, 66) normal (0, 0, 1) x (1, 0, 0) in component "08 Removable battery cradle"
sketch "Pack edge guard" plane through (0, 0, 66) normal (0, 0, 1) x (1, 0, 0) in component "08 Removable battery cradle"
  line L0 (26, 91) -> (93, 91)
  line L1 (93, 91) -> (93, 94)
  line L2 (93, 94) -> (26, 94)
  line L3 (26, 94) -> (26, 91)
extrude "Pack edge guard (1)" add sketch "Pack edge guard" along normal blind 22 bodies 7 in component "08 Removable battery cradle"
ref_plane "WorkPlane5" through (0, 0, 66) normal (0, 0, 1) x (1, 0, 0) in component "08 Removable battery cradle"
sketch "Pack edge guard (1)" plane through (0, 0, 66) normal (0, 0, 1) x (1, 0, 0) in component "08 Removable battery cradle"
  line L0 (26, 139) -> (93, 139)
  line L1 (93, 139) -> (93, 142)
  line L2 (93, 142) -> (26, 142)
  line L3 (26, 142) -> (26, 139)
extrude "Pack edge guard (2)" add sketch "Pack edge guard (1)" along normal blind 22 bodies 7 in component "08 Removable battery cradle"
ref_plane "WorkPlane6" through (0, 0, 88) normal (0, 0, 1) x (1, 0, 0) in component "08 Removable battery cradle"
sketch "Soft strap slot" plane through (0, 0, 88) normal (0, 0, 1) x (1, 0, 0) in component "08 Removable battery cradle"
  line L0 (52, 95) -> (64, 95)
  line L1 (64, 95) -> (64, 98)
  line L2 (64, 98) -> (52, 98)
  line L3 (52, 98) -> (52, 95)
extrude "Soft strap slot (1)" cut sketch "Soft strap slot" along normal blind 2 bodies 7 in component "08 Removable battery cradle"
ref_plane "WorkPlane7" through (0, 0, 88) normal (0, 0, 1) x (1, 0, 0) in component "08 Removable battery cradle"
sketch "Soft strap slot (1)" plane through (0, 0, 88) normal (0, 0, 1) x (1, 0, 0) in component "08 Removable battery cradle"
  line L0 (52, 136) -> (64, 136)
  line L1 (64, 136) -> (64, 139)
  line L2 (64, 139) -> (52, 139)
  line L3 (52, 139) -> (52, 136)
extrude "Soft strap slot (2)" cut sketch "Soft strap slot (1)" along normal blind 2 bodies 7 in component "08 Removable battery cradle"
ref_plane "WorkPlane8" through (0, 0, 88) normal (0, 0, 1) x (1, 0, 0) in component "08 Removable battery cradle"
sketch "Cradle M3 through hole" plane through (0, 0, 88) normal (0, 0, 1) x (1, 0, 0) in component "08 Removable battery cradle"
  circle A0 centre (19, 94) radius 1.7
extrude "Cradle M3 through hole (1)" cut sketch "Cradle M3 through hole" along normal blind 2 bodies 7 in component "08 Removable battery cradle"
ref_plane "WorkPlane18" through (0, 0, 90) normal (0, 0, 1) x (1, 0, 0) in component "03 Ivory rear cover"
sketch "Cradle spacer" plane through (0, 0, 90) normal (0, 0, 1) x (1, 0, 0) in component "03 Ivory rear cover"
  circle A0 centre (19, 94) radius 3.5
extrude "Cradle spacer (1)" add sketch "Cradle spacer" along normal blind 2 bodies 3 in component "03 Ivory rear cover"
ref_plane "WorkPlane19" through (0, 0, 90) normal (0, 0, 1) x (1, 0, 0) in component "03 Ivory rear cover"
sketch "Cradle rear fixing" plane through (0, 0, 90) normal (0, 0, 1) x (1, 0, 0) in component "03 Ivory rear cover"
  circle A0 centre (19, 94) radius 1.7
extrude "Cradle rear fixing (1)" cut sketch "Cradle rear fixing" along normal blind 5 bodies 3 in component "03 Ivory rear cover"
ref_plane "WorkPlane9" through (0, 0, 88) normal (0, 0, 1) x (1, 0, 0) in component "08 Removable battery cradle"
sketch "Cradle M3 through hole (1)" plane through (0, 0, 88) normal (0, 0, 1) x (1, 0, 0) in component "08 Removable battery cradle"
  circle A0 centre (19, 139) radius 1.7
extrude "Cradle M3 through hole (2)" cut sketch "Cradle M3 through hole (1)" along normal blind 2 bodies 7 in component "08 Removable battery cradle"
ref_plane "WorkPlane20" through (0, 0, 90) normal (0, 0, 1) x (1, 0, 0) in component "03 Ivory rear cover"
sketch "Cradle spacer (1)" plane through (0, 0, 90) normal (0, 0, 1) x (1, 0, 0) in component "03 Ivory rear cover"
  circle A0 centre (19, 139) radius 3.5
extrude "Cradle spacer (2)" add sketch "Cradle spacer (1)" along normal blind 2 bodies 3 in component "03 Ivory rear cover"
ref_plane "WorkPlane21" through (0, 0, 90) normal (0, 0, 1) x (1, 0, 0) in component "03 Ivory rear cover"
sketch "Cradle rear fixing (1)" plane through (0, 0, 90) normal (0, 0, 1) x (1, 0, 0) in component "03 Ivory rear cover"
  circle A0 centre (19, 139) radius 1.7
extrude "Cradle rear fixing (2)" cut sketch "Cradle rear fixing (1)" along normal blind 5 bodies 3 in component "03 Ivory rear cover"
ref_plane "WorkPlane10" through (0, 0, 0) normal (0, 1, 0) x (0, 0, 1) in component "08 Removable battery cradle"
sketch "Cradle M3 through hole (2)" plane through (0, 0, 88) normal (0, 0, 1) x (1, 0, 0) in component "08 Removable battery cradle"
  circle A0 centre (98, 94) radius 1.7
extrude "Cradle M3 through hole (3)" cut sketch "Cradle M3 through hole (2)" along normal blind 2 bodies 7 in component "08 Removable battery cradle"
ref_plane "WorkPlane22" through (0, 0, 90) normal (0, 0, 1) x (1, 0, 0) in component "03 Ivory rear cover"
sketch "Cradle spacer (2)" plane through (0, 0, 90) normal (0, 0, 1) x (1, 0, 0) in component "03 Ivory rear cover"
  circle A0 centre (98, 94) radius 3.5
extrude "Cradle spacer (3)" add sketch "Cradle spacer (2)" along normal blind 2 bodies 3 in component "03 Ivory rear cover"
ref_plane "WorkPlane23" through (0, 0, 90) normal (0, 0, 1) x (1, 0, 0) in component "03 Ivory rear cover"
sketch "Cradle rear fixing (2)" plane through (0, 0, 90) normal (0, 0, 1) x (1, 0, 0) in component "03 Ivory rear cover"
  circle A0 centre (98, 94) radius 1.7